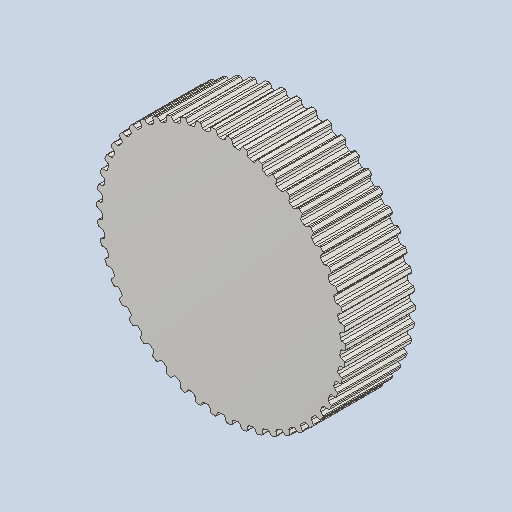
# Autodesk Inventor part: 歯付きプーリ1
Saved by Autodesk Inventor 2025.3 (Build 293356030, 356C)
## iProperties
Created: 2026-02-24
Part Number: 歯付きプーリ1
Material: Steel
Document SubType Name: Modeling
Designer: ibuki_ono
Density: 1 g/cm^3
Appearance: Steel
CustomPartVersion: 1
Author: ibuki_ono
Autodesk Inventor part; units mm, degrees
ref_plane "YZ Plane" through (0, 0, 0) normal (1, 0, 0) x (0, 1, 0)
ref_plane "XZ Plane" through (0, 0, 0) normal (0, 1, 0) x (-1, 0, 0)
ref_plane "XY Plane" through (0, 0, 0) normal (0, 0, 1) x (1, 0, 0)
sketch "プーリ スケッチ" plane through (0, 0, 0) normal (0, 0, 1) x (1, 0, 0)
  circle A0 centre (0, 0) radius 16.1701 construction
  circle A1 centre (0, 0) radius 15.9161
  circle A2 centre (0, 0) radius 15.2303
  line L0 (-0.6637, 15.9023) -> (-0.4191, 15.2303)
  line L1 (-0.4191, 15.2303) -> (0.4191, 15.2303)
  line L2 (0.4191, 15.2303) -> (0.6637, 15.9023)
  line L3 (0, 0) -> (0, 15.9161) construction
  point P0 (0, 15.2303)
  dimension "d0" = 32.3403
  dimension "d1" = 0.254
  dimension "d2" = 0.6858
  dimension "d3" = 40
  dimension "d4" = 0.8382
  constraints: 8 end point, 3 coincident, 3 point on circle, 2 centre point, 1 horizontal, 1 midpoint, 1 point on line, 1 vertical, 1 vertical alignment, 3 other
  measures "d0" diameter of A0
  measures "d1" radial gap between concentric circles of A0 A1
  measures "d3" angle of L2 L0
  measures "d4" distance of L0.end L1.end
extrude "基本ボディ" add sketch "プーリ スケッチ" along normal mid plane 8.89 contours A2 | A1 L0 L1 L2 | L2 L1 L0 A1
extrude "歯" cut sketch "プーリ スケッチ" along normal through all both and the other way through all contours L2 L1 L0 A1 picked at (0, 15.6865)
fillet "Fillet" radius 0.254 2 edges at (0.4191, 15.2303, 0) (-0.4191, 15.2303, 0)
fillet "Fillet" radius 0.127 4 edges at (-0.6637, 15.9023, 2.2225) (-0.6637, 15.9023, -2.2225) (0.6637, 15.9023, 2.2225) (0.6637, 15.9023, -2.2225)
pattern_circular "Teeth" count 50 over 360 about axis through (0, 0, -10) along (0, 0, 1) of "歯", "Fillet"
feature "左フランジ" [suppressed]
feature "右フランジ" [suppressed]
equation "\"d1\" = da_a"
equation "\"d2\" = da_hg"
equation "\"d3\" = 2 * da_fi"
equation "\"d4\" = da_bw"
equation "\"d5\" = da_bf"
equation "\"d7\" = da_bf"
equation "\"d9\" = da_rb"
equation "\"d10\" = da_rt"
equation "\"da_pb\" = 2.032"
equation "\"da_fi\" = 20deg"
equation "\"da_hg\" = 0.6858"
equation "\"da_bw\" = 0.8382"
equation "\"da_rb\" = 0.254"
equation "\"da_rt\" = 0.127"
equation "\"da_a\" = 0.254"
equation "\"da_bf\" = 8.89"
equation "\"da_wf\" = 1.5"
equation "\"da_hf\" = 1.5"
body "Solid1"
